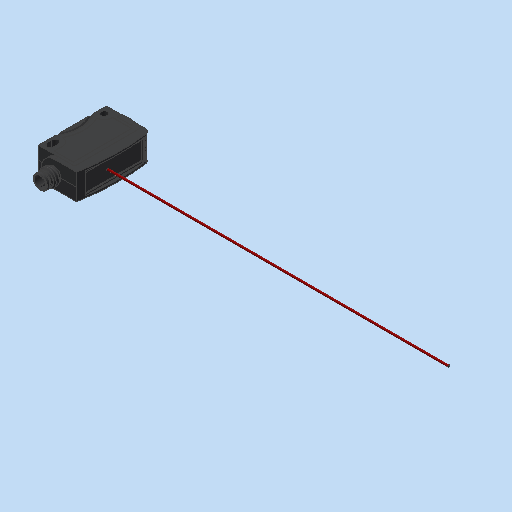
# Autodesk Inventor part: MM0861AN115_G02_107
Saved by Autodesk Inventor 2023.3 (Build 273359000, 359)
## iProperties
Created: 2017-06-19
Part Number: MM0861AN115_G02_107
Catalog Web Link: www.cadenas.de
Description: =<RBPARTNOTITLE2>
Vendor: Balluff
Document SubType Name: Modeling
Designer: psAdmin
Manufacturer: BALLUFF
Mass: 70.9391 g
Surface Area: 39.095 cm^2
Volume: 8.06126 cm^3
Density: 8.8 g/cm^3
Material: Generisch
Appearance: Blau-M
Category: PARTsolutions
Company: BALLUFF
PSOL_IDENT_0: {$CADENAS_DATA\23d-libs\balluff\optoelektronisch\bos_6k.prj},203 {VTYP=3D},{NB=BALLUFF BOS_6K-PU-LK1
PSOL_IDENT_1: 0-S491},{LINA=BALLUFF BOS_6K-PU-LK10-S491},{NN=BOS 6K_1},{DATE=23.01.2017 09:50:01},{GEOMDATE=23.01.
PSOL_IDENT_2: 2017 09:50:01},{VERSION=v1},{LINEID=10510},{LINESUBID=-1},{WBVAR=}  {NB=BALLUFF BOS_6K-PU-LK10-S491}
PSOL_IDENT_3: ,{LINA=BALLUFF BOS_6K-PU-LK10-S491},{KT=DUMMY},{BC=BOS01MN},{AB=BOS 6K-PU-LK10-S49},{PDF=},{LI=},{PX=
PSOL_IDENT_4: 51489_00},{SER=BOS 6K},{TW=},{RW=},{V=22.000},{CLRX=1},{AB1=BOS_6K-PU-LK10-S49},{CLR=0.16,0.45,0.70,
PSOL_IDENT_5: 0.00},{PV=PV120958}
NN: BOS 6K_1
NB: BALLUFF BOS_6K-PU-LK10-S491
NBSYN: BALLUFF $AB1.1
LINA: BALLUFF BOS_6K-PU-LK10-S491
BC: BOS01MN
AB: BOS 6K-PU-LK10-S49
PX: 51489_00
SER: BOS 6K
SUPPLIER: BALLUFF
ARTICLENO: BALLUFF BOS_6K-PU-LK10-S491
BOMINFO: BALLUFF BOS_6K-PU-LK10-S491
CREATOR: CADENAS GmbH
AnP_Kommentar_aktuell: =<Comments>
AnP_Material_aktuell: =<Material>
RBPARTNOTITLE1: reflex switch
RBPARTNOTITLE2: Reflexionslichtschranke
RBDRAWINGMISSINGSPEC: --
AnP_Material: =<Material>
AnP_Kategorie: 11
RBPARTMADEOF: BOS 6K-PU-LK10-S49
RBMATERIAL: --
RBMATNO: =<Part Number>
Title: BALLUFF BOS_6K-PU-LK10-S491
Author: Cadenas PARTsolutions
Keywords: =<RBPARTMADEOF>
Comments: =<RBSURFACE2>
Revision Number: 01
Autodesk Inventor part; units mm, degrees
ref_plane "YZ Plane" through (0, 0, 0) normal (1, 0, 0) x (0, 1, 0)
ref_plane "XZ Plane" through (0, 0, 0) normal (0, 1, 0) x (-1, 0, 0)
ref_plane "XY Plane" through (0, 0, 0) normal (0, 0, 1) x (1, 0, 0)
sketch "Sketch_1" plane through (0, 0, 0) normal (0, 0, 1) x (1, 0, 0)
  arc A0 (-9.5, 0.15) -> (-9.35, 0) centre (-9.35, 0.15) ccw
  line L0 (-9.35, 0) -> (10.2494, 0)
  arc A1 (10.2494, 0) -> (10.3968, 0.1224) centre (10.2494, 0.15) ccw
  arc A2 (10.3968, 0.1224) -> (11.1951, 31.9221) centre (-87.9, 18.5) ccw
  arc A3 (11.1951, 31.9221) -> (8.8169, 34) centre (8.8169, 31.6) ccw
  line L1 (8.8169, 34) -> (-9.5, 34)
  line L2 (-9.5, 34) -> (-9.5, 0.15)
  constraints: 8 point on circle, 6 end point, 4 centre point
extrude "Extrusion1" add sketch "Sketch_1" along normal mid plane 12
sketch "Sketch_12" plane through (0, 0, 6) normal (0, 0, 1) x (1, 0, 0)
  line L0 (-9.5, 2.16) -> (0, 2.16)
  line L1 (0, 2.16) -> (0, 2.11)
  line L2 (0, 2.11) -> (7, 2.11)
  arc A0 (7, 2.11) -> (7.5, 2.61) centre (7, 2.61) ccw
  line L3 (7.5, 2.61) -> (7.5, 34.11)
  line L4 (7.5, 34.11) -> (-9.5, 34.11)
  line L5 (-9.5, 34.11) -> (-9.5, 2.16)
  constraints: 12 end point, 2 point on circle, 1 centre point
extrude "Extrusion2" cut sketch "Sketch_12" against normal blind 0.05
sketch "Sketch_13" plane through (0, 0, 6) normal (0, 0, 1) x (1, 0, 0)
  line L0 (-9.5, 2.11) -> (0, 2.11)
  line L1 (0, 2.11) -> (0, 2.16)
  line L2 (0, 2.16) -> (6.95, 2.16)
  arc A0 (6.95, 2.16) -> (7.45, 2.66) centre (6.95, 2.66) ccw
  line L3 (7.45, 2.66) -> (7.45, 33.96)
  line L4 (7.45, 33.96) -> (-9.5, 33.96)
  line L5 (-9.5, 33.96) -> (-9.5, 2.11)
  constraints: 12 end point, 2 point on circle, 1 centre point
extrude "Extrusion3" add sketch "Sketch_13" against normal blind 0.05
sketch "Sketch_14" plane through (0, 0, -6) normal (0, 0, 1) x (1, 0, 0)
  line L0 (-9.5, 2.16) -> (0, 2.16)
  line L1 (0, 2.16) -> (0, 2.11)
  line L2 (0, 2.11) -> (7, 2.11)
  arc A0 (7, 2.11) -> (7.5, 2.61) centre (7, 2.61) ccw
  line L3 (7.5, 2.61) -> (7.5, 34.11)
  line L4 (7.5, 34.11) -> (-9.5, 34.11)
  line L5 (-9.5, 34.11) -> (-9.5, 2.16)
  constraints: 12 end point, 2 point on circle, 1 centre point
extrude "Extrusion4" cut sketch "Sketch_14" along normal blind 0.05
sketch "Sketch_15" plane through (0, 0, -6) normal (0, 0, 1) x (1, 0, 0)
  line L0 (-9.5, 2.11) -> (0, 2.11)
  line L1 (0, 2.11) -> (0, 2.16)
  line L2 (0, 2.16) -> (6.95, 2.16)
  arc A0 (6.95, 2.16) -> (7.45, 2.66) centre (6.95, 2.66) ccw
  line L3 (7.45, 2.66) -> (7.45, 33.96)
  line L4 (7.45, 33.96) -> (-9.5, 33.96)
  line L5 (-9.5, 33.96) -> (-9.5, 2.11)
  constraints: 12 end point, 2 point on circle, 1 centre point
extrude "Extrusion5" add sketch "Sketch_15" along normal blind 0.05
sketch "Sketch_16" plane through (0, 34, 0) normal (0, 1, 0) x (1, 0, 0)
  line L0 (-9.5, 6) -> (-9.5, -6)
  line L1 (-9.5, -6) -> (7.5, -6)
  arc A0 (7.5, -6) -> (7.5, 6) centre (-5.865, 0) ccw
  line L2 (7.5, 6) -> (-9.5, 6)
  constraints: 6 end point, 2 point on circle, 1 centre point
extrude "Extrusion6" cut sketch "Sketch_16" against normal blind 0.05
sketch "Sketch_17" plane through (0, 34, 0) normal (0, 1, 0) x (1, 0, 0)
  line L0 (-9.5, 6) -> (-9.5, -6)
  line L1 (-9.5, -6) -> (7.45, -6)
  arc A0 (7.45, -6) -> (7.45, 6) centre (-5.915, 0) ccw
  line L2 (7.45, 6) -> (-9.5, 6)
  constraints: 6 end point, 2 point on circle, 1 centre point
extrude "Extrusion7" add sketch "Sketch_17" against normal blind 0.05
sketch "Sketch_3" plane through (-9.5, 0, 0) normal (1, 0, 0) x (0, 0, -1)
  line L0 (-6, 2.1047) -> (-6, 0)
  line L1 (-6, 0) -> (6, 0)
  line L2 (6, 0) -> (6, 2.1047)
  line L3 (6, 2.1047) -> (0, 2)
  line L4 (0, 2) -> (-6, 2.1047)
  constraints: 10 end point
extrude "Extrusion8" cut sketch "Sketch_3" along normal blind 9.5
sketch "Sketch_2" plane through (0, 0, 0) normal (0, 1, 0) x (-1, 0, 0)
  arc A0 (0, -6) -> (0, 6) centre (0, 0) ccw
  line L0 (0, 6) -> (0, -6)
  constraints: 2 end point, 2 point on circle, 1 centre point
extrude "Extrusion9" add sketch "Sketch_2" along normal blind 2.5
sketch "Sketch_4" plane through (-9.5, 0, 0) normal (1, 0, 0) x (0, 0, -1)
  line L0 (-6, -1) -> (6, -1)
  line L1 (6, -1) -> (6, 0.1047)
  line L2 (6, 0.1047) -> (0, 0)
  line L3 (0, 0) -> (-6, 0.1047)
  line L4 (-6, 0.1047) -> (-6, -1)
  constraints: 10 end point
extrude "Extrusion10" cut sketch "Sketch_4" along normal blind 22
sketch "Sketch_5" plane through (12.1, 0, 0) normal (1, 0, 0) x (0, 0, -1)
  line L0 (-5.1, 30.51) -> (-5.1, 3.86)
  line L1 (-5.1, 3.86) -> (5.1, 3.86)
  line L2 (5.1, 3.86) -> (5.1, 30.51)
  line L3 (5.1, 30.51) -> (-5.1, 30.51)
  constraints: 8 end point
extrude "Extrusion11" cut sketch "Sketch_5" against normal blind 1.1
sketch "Sketch_6" plane through (12.1, 0, 0) normal (1, 0, 0) x (0, 0, -1)
  arc A0 (-4.3, 3.98) -> (-4.15, 3.83) centre (-4.15, 3.98) ccw
  line L0 (-4.15, 3.83) -> (4.15, 3.83)
  arc A1 (4.15, 3.83) -> (4.3, 3.98) centre (4.15, 3.98) ccw
  line L1 (4.3, 3.98) -> (4.3, 30.38)
  arc A2 (4.3, 30.38) -> (4.15, 30.53) centre (4.15, 30.38) ccw
  line L2 (4.15, 30.53) -> (-4.15, 30.53)
  arc A3 (-4.15, 30.53) -> (-4.3, 30.38) centre (-4.15, 30.38) ccw
  line L3 (-4.3, 30.38) -> (-4.3, 3.98)
  constraints: 8 end point, 8 point on circle, 4 centre point
extrude "Extrusion12" cut sketch "Sketch_6" against normal blind 1.6
sketch "Sketch_7" plane through (0, 0, 0) normal (0, 0, 1) x (1, 0, 0)
  circle A0 centre (-6.9, 30.4) radius 1.6
  constraints: 1 centre point
extrude "Extrusion13" cut sketch "Sketch_7" along normal mid plane 12
sketch "Sketch_8" plane through (0, 0, 0) normal (0, 0, 1) x (1, 0, 0)
  arc A0 (-8.5, 5) -> (-5.3, 5) centre (-6.9, 5) ccw
  line L0 (-5.3, 5) -> (-5.3, 7.5)
  arc A1 (-5.3, 7.5) -> (-8.5, 7.5) centre (-6.9, 7.5) ccw
  line L1 (-8.5, 7.5) -> (-8.5, 5)
  constraints: 4 end point, 4 point on circle, 2 centre point
extrude "Extrusion14" cut sketch "Sketch_8" along normal mid plane 12
sketch "Sketch_9" plane through (0, 0, 6) normal (0, 0, 1) x (1, 0, 0)
  arc A0 (-6.89, 11.1154) -> (-6.7625, 10.8972) centre (-6.7564, 11.0471) ccw
  arc A1 (-3.5, 7.5) -> (-6.7625, 10.8972) centre (-6.9, 7.5) ccw
  line L0 (-3.5, 7.5) -> (-3.5, 3.65)
  arc A2 (-3.5, 3.65) -> (-3.35, 3.5) centre (-3.35, 3.65) ccw
  line L1 (-3.35, 3.5) -> (5.35, 3.5)
  arc A3 (5.35, 3.5) -> (5.5, 3.65) centre (5.35, 3.65) ccw
  line L2 (5.5, 3.65) -> (5.5, 30.7)
  arc A4 (5.5, 30.7) -> (5.35, 30.85) centre (5.35, 30.7) ccw
  line L3 (5.35, 30.85) -> (-3.3627, 30.85)
  arc A5 (-3.3627, 30.85) -> (-3.5122, 30.6873) centre (-3.3627, 30.7) ccw
  arc A6 (-6.715, 27.005) -> (-3.5122, 30.6873) centre (-6.9, 30.4) ccw
  arc A7 (-6.715, 27.005) -> (-6.8408, 26.7878) centre (-6.7068, 26.8553) ccw
  arc A8 (-6.89, 11.1154) -> (-6.8408, 26.7878) centre (-22.3, 19) ccw
  constraints: 18 point on circle, 9 centre point, 8 end point
extrude "Extrusion15" cut sketch "Sketch_9" along normal mid plane 0.4
sketch "Sketch_10" plane through (0, 19, 0) normal (0, 1, 0) x (1, 0, 0)
  line L0 (-22.3, 5.3121) -> (-22.3, 6.5)
  line L1 (-8.55, 6.5) -> (-8.55, 6)
  line L2 (-8.55, 6) -> (-8.1121, 6)
  arc A0 (-8.0061, 5.9561) -> (-8.1121, 6) centre (-8.1121, 5.85) ccw
  line L3 (-8.0061, 5.9561) -> (-7.4061, 5.3561)
  arc A1 (-7.4061, 5.3561) -> (-7.1939, 5.3561) centre (-7.3, 5.4621) ccw
  line L4 (-7.1939, 5.3561) -> (-6.5939, 5.9561)
  arc A2 (-6.4879, 6) -> (-6.5939, 5.9561) centre (-6.4879, 5.85) ccw
  line L5 (-6.4879, 6) -> (-6.05, 6)
  line L6 (-6.05, 6) -> (-6.05, 6.5)
  line L7 (-6.05, 6.5) -> (-8.55, 6.5)
  constraints: 16 end point, 6 point on circle, 3 centre point
revolve "Revolution1" cut sketch "Sketch_10" angle 80 mid plane about axis through (-22.3, 19, -5.3121) along (0, 0, -1)
sketch "Sketch_11" plane through (0, 19, 0) normal (0, 1, 0) x (1, 0, 0)
  line L0 (-22.3, -6.5) -> (-22.3, -5.3121)
  line L1 (-8.55, -6.5) -> (-6.05, -6.5)
  line L2 (-6.05, -6.5) -> (-6.05, -6)
  line L3 (-6.05, -6) -> (-6.4879, -6)
  arc A0 (-6.5939, -5.9561) -> (-6.4879, -6) centre (-6.4879, -5.85) ccw
  line L4 (-6.5939, -5.9561) -> (-7.1939, -5.3561)
  arc A1 (-7.1939, -5.3561) -> (-7.4061, -5.3561) centre (-7.3, -5.4621) ccw
  line L5 (-7.4061, -5.3561) -> (-8.0061, -5.9561)
  arc A2 (-8.1121, -6) -> (-8.0061, -5.9561) centre (-8.1121, -5.85) ccw
  line L6 (-8.1121, -6) -> (-8.55, -6)
  line L7 (-8.55, -6) -> (-8.55, -6.5)
  constraints: 16 end point, 6 point on circle, 3 centre point
revolve "Revolution2" cut sketch "Sketch_11" angle 100 mid plane about axis through (-22.3, 19, 6.5) along (0, 0, -1)
sketch "Sketch_18" plane through (0, 0, 0) normal (0, 0, 1) x (1, 0, 0)
  line L0 (0, -6.6) -> (0, 0.5)
  line L1 (0, 0.5) -> (3.25, 0.5)
  line L2 (3.25, 0.5) -> (3.25, -0.9)
  line L3 (3.25, -0.9) -> (3.3865, -0.9)
  line L4 (3.3865, -0.9) -> (4, -1.5135)
  line L5 (4, -1.5135) -> (4, -2.9865)
  line L6 (4, -2.9865) -> (3.3865, -3.6)
  line L7 (3.3865, -3.6) -> (3.25, -3.6)
  line L8 (3.25, -3.6) -> (3.25, -4.6)
  line L9 (3.25, -4.6) -> (3.45, -4.85)
  line L10 (3.45, -4.85) -> (3.45, -5.35)
  line L11 (3.45, -5.35) -> (3.2769, -6.4316)
  arc A0 (3.0795, -6.6) -> (3.2769, -6.4316) centre (3.0795, -6.4) ccw
  line L12 (3.0795, -6.6) -> (0, -6.6)
  line L13 (0, -6.6) -> (0, 0.5)
  constraints: 28 end point, 2 point on circle, 1 centre point
revolve "Revolution3" add sketch "Sketch_18" angle 360 about axis through (0, -6.6, 0) along (0, -1, 0)
thread "Thread1" size "M8x1" class "6g" standard "ISO Metric profile" full length
sketch "Sketch19" plane through (0, -6.6, 0) normal (0, -1, 0) x (1, 0, 0)
  point P0 (0, 0)
hole "Hole1" at (0, -6.6, 0) direction (0, 1, 0) diameter 5.8 depth 5
sketch "Sketch20" plane through (0, 34, 0) normal (0, 1, 0) x (1, 0, 0)
  point P0 (-0.4, 0)
hole "Hole2" at (-0.4, 34, 0) direction (0, -1, 0) diameter 4.1 depth 0.2
sketch "Sketch_25" plane through (0, 0, 0) normal (0, 0, 1) x (1, 0, 0)
  line L0 (-0.4, 33.8) -> (-0.4, 34.6)
  line L1 (-0.4, 34.6) -> (-0.2303, 34.6)
  arc A0 (-0.2303, 34.6) -> (-0.1018, 34.6468) centre (-0.2303, 34.8) ccw
  line L2 (-0.1018, 34.6468) -> (0.2, 34.9)
  line L3 (0.2, 34.9) -> (1.3343, 34.9)
  arc A1 (1.5342, 34.7035) -> (1.3343, 34.9) centre (1.3343, 34.7) ccw
  line L4 (1.5342, 34.7035) -> (1.55, 33.8)
  line L5 (1.55, 33.8) -> (-0.4, 33.8)
  line L6 (-0.4, 33.8) -> (-0.4, 34.6)
  constraints: 14 end point, 4 point on circle, 2 centre point
revolve "Revolution4" add sketch "Sketch_25" angle 360 about axis through (-0.4, 33.8, 0) along (0, -1, 0)
sketch "Sketch_26" plane through (12.1, 0, 0) normal (1, 0, 0) x (0, 0, -1)
  line L0 (-5.17, 30.84) -> (-4.0654, 30.84)
  arc A0 (-4.0654, 30.84) -> (-3.8725, 31.6154) centre (-4.0862, 31.2569) ccw
  arc A1 (-3.8725, 31.6154) -> (-4.138, 32.34) centre (-4.1203, 31.9355) ccw
  line L1 (-4.138, 32.34) -> (-5.17, 32.34)
  line L2 (-5.17, 32.34) -> (-5.17, 30.84)
  line L3 (-4.737, 31.7595) -> (-4.331, 31.7595)
  arc A2 (-4.331, 31.7595) -> (-4.3465, 32.0018) centre (-4.3225, 31.8817) ccw
  line L4 (-4.3465, 32.0018) -> (-4.737, 32.0018)
  line L5 (-4.737, 32.0018) -> (-4.737, 31.7595)
  line L6 (-4.737, 31.4599) -> (-4.737, 31.1956)
  line L7 (-4.737, 31.1956) -> (-4.3179, 31.1955)
  arc A3 (-4.3179, 31.1955) -> (-4.1652, 31.3307) centre (-4.2951, 31.3236) ccw
  arc A4 (-4.1652, 31.3307) -> (-4.3066, 31.4599) centre (-4.288, 31.3381) ccw
  line L8 (-4.3066, 31.4599) -> (-4.737, 31.4599)
  constraints: 18 end point, 10 point on circle, 5 centre point
extrude "Extrusion16" cut sketch "Sketch_26" against normal blind 1.3
sketch "Sketch_27" plane through (12.1, 0, 0) normal (1, 0, 0) x (0, 0, -1)
  line L0 (-3.67, 30.84) -> (-3.1722, 30.84)
  line L1 (-3.1722, 30.84) -> (-2.7309, 31.8886)
  line L2 (-2.7309, 31.8886) -> (-2.4624, 31.2244)
  line L3 (-2.4624, 31.2244) -> (-2.819, 31.2244)
  line L4 (-2.819, 31.2244) -> (-2.819, 30.84)
  line L5 (-2.819, 30.84) -> (-1.7917, 30.84)
  line L6 (-1.7917, 30.84) -> (-2.4661, 32.34)
  line L7 (-2.4661, 32.34) -> (-2.9956, 32.34)
  line L8 (-2.9956, 32.34) -> (-3.67, 30.84)
  constraints: 18 end point
extrude "Extrusion17" cut sketch "Sketch_27" against normal blind 1.2
sketch "Sketch_28" plane through (12.1, 0, 0) normal (1, 0, 0) x (0, 0, -1)
  line L0 (-1.66, 30.84) -> (-0.5625, 30.84)
  line L1 (-0.5625, 30.84) -> (-0.5625, 31.2244)
  line L2 (-0.5625, 31.2244) -> (-1.1938, 31.2244)
  line L3 (-1.1938, 31.2244) -> (-1.1938, 32.34)
  line L4 (-1.1938, 32.34) -> (-1.66, 32.34)
  line L5 (-1.66, 32.34) -> (-1.66, 30.84)
  constraints: 12 end point
extrude "Extrusion18" cut sketch "Sketch_28" against normal blind 1.2
sketch "Sketch_29" plane through (12.1, 0, 0) normal (1, 0, 0) x (0, 0, -1)
  line L0 (-0.4, 30.84) -> (0.6975, 30.84)
  line L1 (0.6975, 30.84) -> (0.6975, 31.2244)
  line L2 (0.6975, 31.2244) -> (0.0662, 31.2244)
  line L3 (0.0662, 31.2244) -> (0.0662, 32.34)
  line L4 (0.0662, 32.34) -> (-0.4, 32.34)
  line L5 (-0.4, 32.34) -> (-0.4, 30.84)
  constraints: 12 end point
extrude "Extrusion19" cut sketch "Sketch_29" against normal blind 1.2
sketch "Sketch_30" plane through (12.1, 0, 0) normal (1, 0, 0) x (0, 0, -1)
  line L0 (0.8411, 32.34) -> (0.8411, 31.2046)
  arc A0 (0.8411, 31.2046) -> (1.2073, 30.84) centre (1.2073, 31.2063) ccw
  line L1 (1.2073, 30.84) -> (1.9536, 30.84)
  arc A1 (1.9536, 30.84) -> (2.3204, 31.2046) centre (1.9536, 31.2068) ccw
  line L2 (2.3204, 31.2046) -> (2.3204, 32.34)
  line L3 (2.3204, 32.34) -> (1.8542, 32.34)
  line L4 (1.8542, 32.34) -> (1.8542, 31.2518)
  arc A2 (1.8269, 31.2244) -> (1.8542, 31.2518) centre (1.8269, 31.2518) ccw
  line L5 (1.8269, 31.2244) -> (1.3346, 31.2244)
  arc A3 (1.3073, 31.2518) -> (1.3346, 31.2244) centre (1.3346, 31.2518) ccw
  line L6 (1.3073, 31.2518) -> (1.3073, 32.34)
  line L7 (1.3073, 32.34) -> (0.8411, 32.34)
  constraints: 16 end point, 8 point on circle, 4 centre point
extrude "Extrusion20" cut sketch "Sketch_30" against normal blind 1.2
sketch "Sketch_31" plane through (12.1, 0, 0) normal (1, 0, 0) x (0, 0, -1)
  line L0 (2.5, 30.84) -> (2.966, 30.84)
  line L1 (2.966, 30.84) -> (2.966, 31.3297)
  line L2 (2.966, 31.3297) -> (3.5971, 31.3297)
  line L3 (3.5971, 31.3297) -> (3.5971, 31.6792)
  line L4 (3.5971, 31.6792) -> (2.966, 31.6792)
  line L5 (2.966, 31.6792) -> (2.966, 31.9555)
  line L6 (2.966, 31.9555) -> (3.6865, 31.9555)
  line L7 (3.6865, 31.9555) -> (3.6865, 32.34)
  line L8 (3.6865, 32.34) -> (2.5, 32.34)
  line L9 (2.5, 32.34) -> (2.5, 30.84)
  constraints: 20 end point
extrude "Extrusion21" cut sketch "Sketch_31" against normal blind 1.2
sketch "Sketch_32" plane through (12.1, 0, 0) normal (1, 0, 0) x (0, 0, -1)
  line L0 (3.84, 30.84) -> (4.306, 30.84)
  line L1 (4.306, 30.84) -> (4.306, 31.3297)
  line L2 (4.306, 31.3297) -> (4.9371, 31.3297)
  line L3 (4.9371, 31.3297) -> (4.9371, 31.6792)
  line L4 (4.9371, 31.6792) -> (4.306, 31.6792)
  line L5 (4.306, 31.6792) -> (4.306, 31.9555)
  line L6 (4.306, 31.9555) -> (5.0265, 31.9555)
  line L7 (5.0265, 31.9555) -> (5.0265, 32.34)
  line L8 (5.0265, 32.34) -> (3.84, 32.34)
  line L9 (3.84, 32.34) -> (3.84, 30.84)
  constraints: 20 end point
extrude "Extrusion22" cut sketch "Sketch_32" against normal blind 1.2
sketch "Sketch_35" plane through (0, 0, 3.4) normal (0, 0, 1) x (1, 0, 0)
  line L0 (-2.5433, 34) -> (-2.5433, 32)
  line L1 (-2.5433, 32) -> (4.1833, 32)
  line L2 (4.1833, 32) -> (4.1833, 34)
  arc A0 (4.1833, 34) -> (-2.5433, 34) centre (0.82, 20.41) ccw
  constraints: 6 end point, 2 point on circle, 1 centre point
extrude "Extrusion23" add sketch "Sketch_35" along normal blind 2.65
sketch "Sketch_33" plane through (0, 0, -6.05) normal (0, 0, 1) x (1, 0, 0)
  line L0 (-2.5433, 34) -> (-2.5433, 32)
  line L1 (-2.5433, 32) -> (4.1833, 32)
  line L2 (4.1833, 32) -> (4.1833, 34)
  arc A0 (4.1833, 34) -> (-2.5433, 34) centre (0.82, 20.41) ccw
  constraints: 6 end point, 2 point on circle, 1 centre point
extrude "Extrusion24" add sketch "Sketch_33" along normal blind 2.65
sketch "Sketch_34" plane through (0, 0, 0) normal (0, 0, 1) x (1, 0, 0)
  line L0 (1.75, -6.2) -> (1.75, -1.6)
  line L1 (1.75, -1.6) -> (2.25, -1.6)
  line L2 (2.25, -1.6) -> (2.25, -5.7)
  arc A0 (1.75, -6.2) -> (2.25, -5.7) centre (1.75, -5.7) ccw
  line L3 (1.75, -6.2) -> (1.75, -1.6)
  constraints: 8 end point, 2 point on circle, 1 centre point
revolve "Revolution5" add sketch "Sketch_34" angle 360 about axis through (1.75, -6.2, 0) along (0, -1, 0)
sketch "Sketch_36" plane through (0, 0, 0) normal (1, 0, 0) x (0, 1, 0)
  line L0 (-6.2, -1.75) -> (-1.6, -1.75)
  line L1 (-1.6, -1.75) -> (-1.6, -2.25)
  line L2 (-1.6, -2.25) -> (-5.7, -2.25)
  arc A0 (-6.2, -1.75) -> (-5.7, -2.25) centre (-5.7, -1.75) ccw
  line L3 (-6.2, -1.75) -> (-1.6, -1.75)
  constraints: 8 end point, 2 point on circle, 1 centre point
revolve "Revolution6" add sketch "Sketch_36" angle 360 about axis through (0, -6.2, -1.75) along (0, -1, 0)
sketch "Sketch_37" plane through (0, 0, 0) normal (1, 0, 0) x (0, 1, 0)
  line L0 (-6.2, 1.75) -> (-1.6, 1.75)
  line L1 (-1.6, 1.75) -> (-1.6, 1.25)
  line L2 (-1.6, 1.25) -> (-5.7, 1.25)
  arc A0 (-6.2, 1.75) -> (-5.7, 1.25) centre (-5.7, 1.75) ccw
  line L3 (-6.2, 1.75) -> (-1.6, 1.75)
  constraints: 8 end point, 2 point on circle, 1 centre point
revolve "Revolution7" add sketch "Sketch_37" angle 360 about axis through (0, -6.2, 1.75) along (0, -1, 0)
sketch "Skizze34" plane through (10.5, 0, 0) normal (1, 0, 0) x (0, 0, -1)
  line L0 (-8.47, 0) -> (8.47, 0) projected
  line L1 (0, -14.9) -> (0, 43.2) projected
  circle A0 centre (0, 14.6) radius 0.5
  dimension "d71" = 1
  dimension "d72" = 14.6
  constraints: 1 centre point, 1 point on line
  measures "d71" diameter of A0
  measures "d72" distance from line of L0 A0.centre
extrude "Extrusion25" add sketch "Skizze34" along normal blind 160
body "Solid1"
